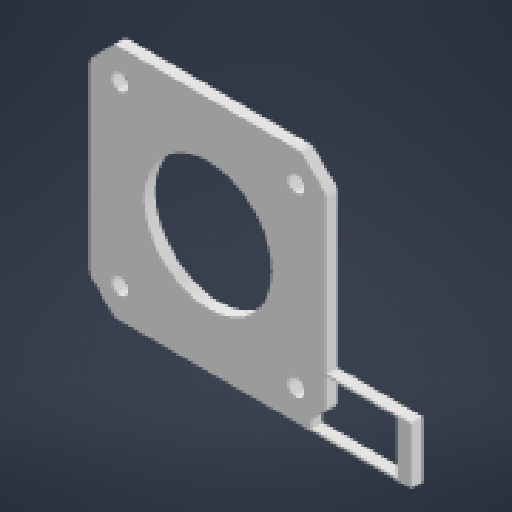
# Autodesk Inventor part: gia_gan_stepper_va_2040
Saved by Autodesk Inventor 2026.2 (Build 302298000, 298)
## iProperties
Created: 2026-07-05
Part Number: gia_gan_stepper_va_2040
Material: Generic
Document SubType Name: Modeling
Designer: thita
Density: 1 g/cm^3
Appearance: Default
Author: thita
Autodesk Inventor part; units mm, degrees
ref_plane "YZ Plane" through (0, 0, 0) normal (1, 0, 0) x (0, 1, 0)
ref_plane "XZ Plane" through (0, 0, 0) normal (0, 1, 0) x (-1, 0, 0)
ref_plane "XY Plane" through (0, 0, 0) normal (0, 0, 1) x (1, 0, 0)
sketch "Sketch1" plane through (0, 0, 0) normal (0, 0, 1) x (1, 0, 0)
  line L0 (20.8, -15.6716) -> (20.8, 15.6716)
  arc A0 (20.8, 15.6716) -> (20.2728, 16.9444) centre (19, 15.6716) ccw
  line L1 (20.2728, 16.9444) -> (16.9444, 20.2728)
  arc A1 (16.9444, 20.2728) -> (15.6716, 20.8) centre (15.6716, 19) ccw
  line L2 (15.6716, 20.8) -> (-15.6716, 20.8)
  arc A2 (-15.6716, 20.8) -> (-16.9444, 20.2728) centre (-15.6716, 19) ccw
  line L3 (-16.9444, 20.2728) -> (-20.2728, 16.9444)
  arc A3 (-20.2728, 16.9444) -> (-20.8, 15.6716) centre (-19, 15.6716) ccw
  line L4 (-20.8, 15.6716) -> (-20.8, -15.6716)
  arc A4 (-20.8, -15.6716) -> (-20.2728, -16.9444) centre (-19, -15.6716) ccw
  line L5 (-20.2728, -16.9444) -> (-16.9444, -20.2728)
  arc A5 (-16.9444, -20.2728) -> (-15.6716, -20.8) centre (-15.6716, -19) ccw
  line L6 (-15.6716, -20.8) -> (15.6716, -20.8)
  arc A6 (15.6716, -20.8) -> (16.9444, -20.2728) centre (15.6716, -19) ccw
  line L7 (16.9444, -20.2728) -> (20.2728, -16.9444)
  arc A7 (20.2728, -16.9444) -> (20.8, -15.6716) centre (19, -15.6716) ccw
  circle A8 centre (0, 0) radius 11.2
  circle A9 centre (15.5, 15.5) radius 1.45
  circle A10 centre (-15.5, 15.5) radius 1.45
  circle A11 centre (-15.5, -15.5) radius 1.45
  circle A12 centre (15.5, -15.5) radius 1.45
  constraints: 16 end point, 16 point on circle, 13 centre point
extrude "Extrusion1" add sketch "Sketch1" along normal blind 2
sketch "Sketch2" plane through (0, 0, 0) normal (0, 0, -1) x (-1, 0, 0)
  arc A0 (-16.9444, -20.2728) -> (-15.6716, -20.8) centre (-15.6716, -19) ccw projected
  line L0 (-15.6716, -20.8) -> (-35.6716, -20.8)
  line L1 (-35.6716, -20.8) -> (-35.6716, -10.8)
  line L2 (-35.6716, -10.8) -> (-15.6716, -10.8)
  arc A1 (-15.6716, -14.0602) -> (-15.6716, -16.9398) centre (-15.5, -15.5) ccw
  line L3 (-15.6716, -10.8) -> (-15.6716, -14.0602)
  line L4 (-15.6716, -16.9398) -> (-15.6716, -20.8)
  line L5 (-35.6716, -15.8) -> (-25.6716, -15.8)
  line L6 (-18.1716, -11.198) -> (-18.1716, -20.402)
  line L7 (-18.1716, -20.402) -> (-33.1716, -20.402)
  line L8 (-33.1716, -20.402) -> (-33.1716, -11.198)
  line L9 (-33.1716, -11.198) -> (-18.1716, -11.198)
  line L10 (-18.1716, -11.198) -> (-33.1716, -20.402) construction
  line L11 (-18.1716, -20.402) -> (-33.1716, -11.198) construction
  point P0 (0, 0)
  dimension "d2" = 20
  dimension "d3" = 10
  dimension "d4" = 9.204
  dimension "d5" = 15
  constraints: 24 end point, 5 perpendicular, 3 midpoint, 2 horizontal, 2 parallel, 2 point on circle, 1 centre point, 1 tangent, 1 vertical
  measures "d2" distance of L0.start L0.end
  measures "d3" distance of L0.end L1.end
  measures "d4" distance of L6.start L6.end
  measures "d5" distance of L6.end L7.end
extrude "Extrusion2" add sketch "Sketch2" against normal blind 2
body "Solid1"
